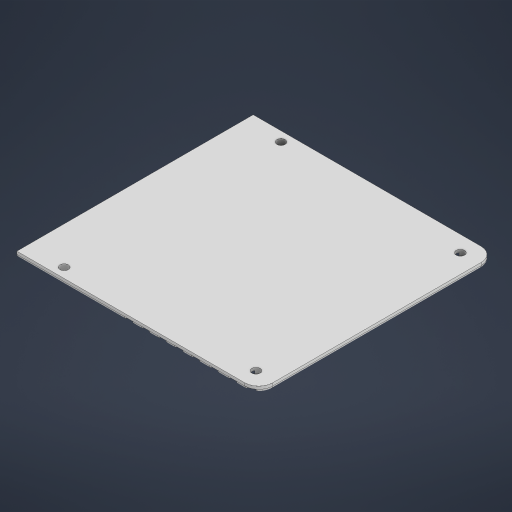
# Autodesk Inventor part: Крышка2
Saved by Autodesk Inventor 2024 (Build 280153000, 153)
## iProperties
Created: 2026-05-30
Part Number: Крышка2
Material: Типовые
Document SubType Name: Modeling
Designer: mitm
Density: 1 g/cm^3
Appearance: По умолчанию
Author: mitm
Autodesk Inventor part; units mm, degrees
ref_plane "YZ Plane" through (0, 0, 0) normal (1, 0, 0) x (0, 1, 0)
ref_plane "XZ Plane" through (0, 0, 0) normal (0, 1, 0) x (-1, 0, 0)
ref_plane "XY Plane" through (0, 0, 0) normal (0, 0, 1) x (1, 0, 0)
sketch "Эскиз1" plane through (0, 0, 0) normal (0, 1, 0) x (-1, 0, 0)
  line L0 (39, 42.5) -> (-29, 42.5)
  line L1 (-39, 32.5) -> (-39, -32.5)
  line L2 (-29, -42.5) -> (39, -42.5)
  line L3 (-29, 42.5) -> (-34, 42.5)
  line L4 (-39, 37.5) -> (-39, 32.5)
  circle A0 centre (-32.25, 36.75) radius 1.5
  line L5 (-29, -42.5) -> (-34, -42.5)
  line L6 (-39, -32.5) -> (-39, -37.5)
  arc A1 (-34, 42.5) -> (-39, 37.5) centre (-34, 37.5) ccw
  arc A2 (-39, -37.5) -> (-34, -42.5) centre (-34, -37.5) ccw
  circle A3 centre (34.5, 39) radius 1.5
  circle A4 centre (34.5, -39) radius 1.5
  circle A5 centre (-32.25, -36.75) radius 1.5
  line L7 (48, 0) -> (48, -42.5)
  line L8 (48, -42.5) -> (39, -42.5)
  line L9 (48, 0) -> (48, 42.5)
  line L10 (48, 42.5) -> (39, 42.5)
  dimension "d11" = 3
  dimension "d12" = 5
  dimension "d18" = 3
  dimension "d20" = 3
  constraints: 22 end point, 6 centre point, 4 perpendicular, 4 point on circle, 4 tangent, 2 horizontal, 1 equal radius, 1 parallel, 1 point on line
  measures "d11" diameter of A0
  measures "d12" radius of A1
  measures "d18" diameter of A4
  measures "d20" diameter of A5
extrude "Выдавливание1" add sketch "Эскиз1" against normal blind 2
fillet "Сопряжение1" radius 1 5 edges at (37.5355, -2, -41.0355) (39, -2, 0) (37.5355, -2, 41.0355) (-5, -2, 42.5) (-5, -2, -42.5)
sketch "Эскиз2" plane through (0, -2, 0) normal (0, -1, 0) x (1, 0, 0)
  line L0 (38, -53.7641) -> (37, -53.7641)
  line L1 (37, -53.7641) -> (37, 53.9513)
  line L2 (38, 37.5) -> (38, -37.5) projected
  line L3 (37, 53.9513) -> (34, 53.9513)
  line L4 (34, 53.9513) -> (34, -53.7641)
  line L5 (34, -53.7641) -> (31, -53.7641)
  line L6 (31, -53.7641) -> (31, 53.9513)
  line L7 (31, 53.9513) -> (28, 53.9513)
  line L8 (28, 53.9513) -> (27.3303, -53.7641)
  line L9 (27.3303, -53.7641) -> (24.3303, -53.7641)
  line L10 (24.3303, -53.7641) -> (24.3303, 53.9513)
  line L11 (24.3303, 53.9513) -> (21.3303, 53.9513)
  line L12 (21.3303, 53.9513) -> (20.6607, -53.7641)
  line L13 (20.6607, -53.7641) -> (17.6607, -53.7641)
  line L14 (17.6607, -53.7641) -> (17.6607, 53.9513)
  line L15 (17.6607, 53.9513) -> (14.6607, 53.9513)
  line L16 (14.6607, 53.9513) -> (14.6607, -53.7641)
  line L17 (14.6607, -53.7641) -> (11.6607, -53.7641)
  line L18 (11.6607, -53.7641) -> (11.6607, 53.9513)
  line L19 (11.6607, 53.9513) -> (8.6607, 53.9513)
  line L20 (8.6607, 53.9513) -> (8.6607, -53.7641)
  line L21 (8.6607, -53.7641) -> (5.6607, -53.7641)
  line L22 (5.6607, -53.7641) -> (5.6607, 53.9513)
  line L23 (5.6607, 53.9513) -> (2.6607, 53.9513)
  line L24 (2.6607, 53.9513) -> (2.6607, -53.7641)
  line L25 (2.6607, -53.7641) -> (-0.3393, -53.7641)
  line L26 (-0.3393, -53.7641) -> (-0.3393, 53.9513)
  line L27 (-0.3393, 53.9513) -> (-3.3393, 53.9513)
  line L28 (-3.3393, 53.9513) -> (-3.3393, -53.7641)
  line L29 (-3.3393, -53.7641) -> (-6.3393, -53.7641)
  line L30 (-6.3393, -53.7641) -> (-6.3393, 53.9513)
  line L31 (-6.3393, 53.9513) -> (-9.3393, 53.9513)
  line L32 (-9.3393, 53.9513) -> (-9.3393, -53.7641)
  line L33 (-9.3393, 53.9513) -> (37, 53.9513)
  line L34 (-9.3393, -53.7641) -> (37, -53.7641)
  point P0 (0, 0)
  dimension "d50" = 1
  dimension "d51" = 3
  dimension "d52" = 3
  dimension "d53" = 3
  dimension "d54" = 3
  dimension "d55" = 3
  dimension "d56" = 3
  dimension "d57" = 3
  dimension "d58" = 3
  dimension "d59" = 3
  dimension "d60" = 3
  dimension "d61" = 3
  dimension "d62" = 3
  dimension "d63" = 3
  dimension "d65" = 3
  dimension "d66" = 3
  constraints: 68 end point, 26 point on line, 15 perpendicular, 3 horizontal, 3 parallel
  measures "d50" distance of L0.start L0.end
  measures "d51" distance of L1.end L3.end
  measures "d52" distance of L4.end L5.end
  measures "d53" distance of L6.end L7.end
  measures "d54" distance of L8.end L9.end
  measures "d55" distance of L10.end L11.end
  measures "d56" distance of L12.end L13.end
  measures "d57" distance of L14.end L15.end
  measures "d58" distance of L16.end L17.end
  measures "d59" distance of L18.end L19.end
  measures "d60" distance of L20.end L21.end
  measures "d61" distance of L22.end L23.end
  measures "d62" distance of L24.end L25.end
  measures "d63" distance of L26.end L27.end
  measures "d65" distance of L28.end L29.end
  measures "d66" distance of L30.end L31.end
extrude "Выдавливание2" cut sketch "Эскиз2" against normal blind 1 contours L34 L4 L3 L1 | L34 L8 L7 L6 | L34 L12 L11 L10 | L34 L16 L15 L14 | L34 L20 L19 L18 | L34 L24 L23 L22 | L34 L28 L27 L26 | L34 L32 L31 L30
